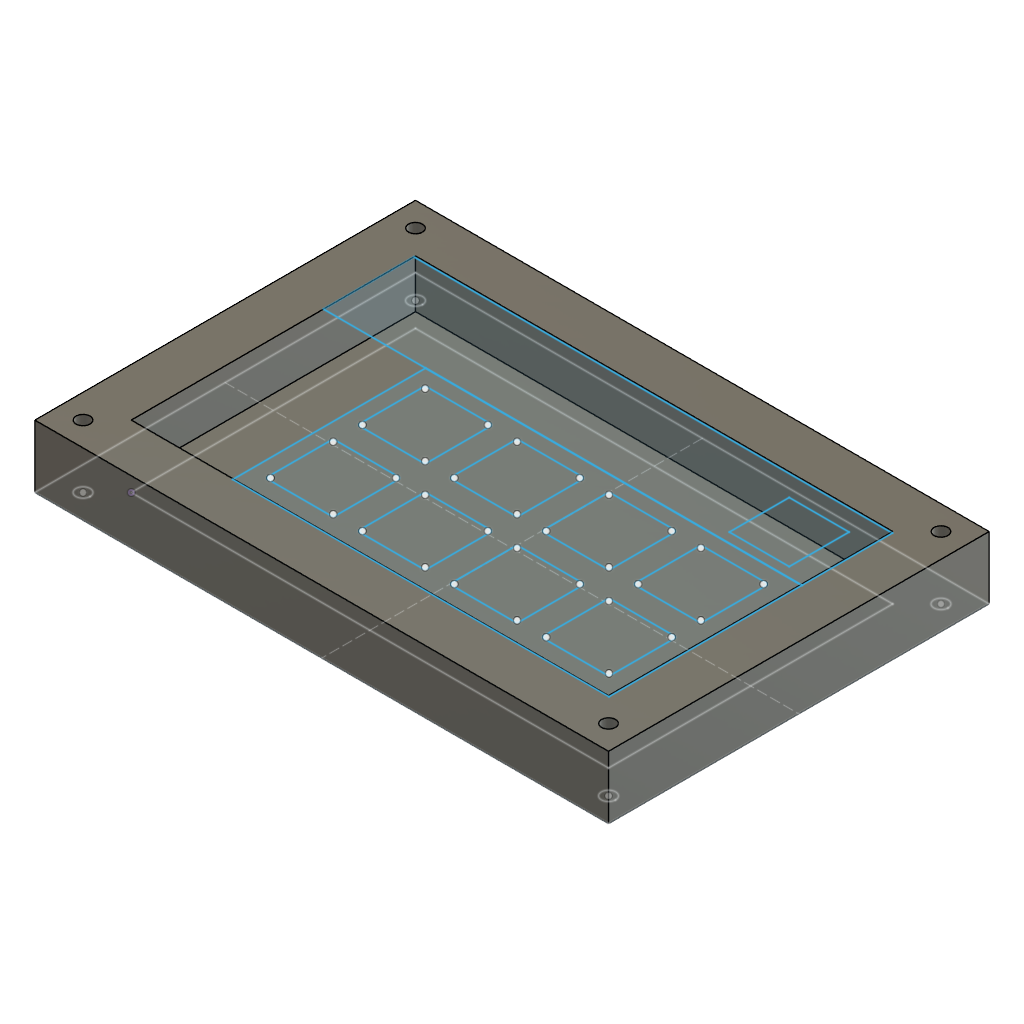
hackpad (Autodesk Fusion 360 design; units mm, degrees)
part number: 2026-11-01-11-27-36-665
Autodesk Fusion 360 part; units mm, degrees
sketch "스케치1" plane through (0, 0, 0) normal (0, 1, 0) x (1, 0, 0)
  line L0 (0, 0) -> (98.9, 0)
  line L1 (98.9, 0) -> (98.9, 58.9)
  line L2 (98.9, 58.9) -> (0, 58.9)
  line L3 (0, 58.9) -> (0, 0)
  line L4 (-10, -10) -> (108.9, -10)
  line L5 (108.9, -10) -> (108.9, 68.9)
  line L6 (108.9, 68.9) -> (-10, 68.9)
  line L7 (-10, 68.9) -> (-10, -10)
  line L8 (49.45, 68.9) -> (49.45, -10) construction
  line L9 (-10, 29.45) -> (108.9, 29.45) construction
  circle A0 centre (-5, 63.9) radius 1.45
  circle A1 centre (103.9, 63.9) radius 1.45
  circle A2 centre (-5, -5) radius 1.45
  circle A3 centre (103.9, -5) radius 1.45
  dimension "d1" = 98.9
  dimension "d2" = 58.9
  dimension "d3" = 118.9
  dimension "d4" = 78.9
  dimension "d5" = 10
  dimension "d6" = 10
  dimension "d7" = 2.9
  dimension "d8" = 5
  dimension "d9" = 5
  dimension "d10" = 2.9
  dimension "d11" = 2.9
  dimension "d12" = 2.9
  constraint horizontal L0
  constraint vertical L1
  constraint horizontal L2
  constraint vertical L3
  constraint coincident L0.start L3.end
  constraint horizontal L4
  constraint vertical L5
  constraint horizontal L6
  constraint vertical L7
  constraint midpoint L6 L8.start
  constraint midpoint L4 L8.end
  constraint midpoint L7 L9.start
  constraint midpoint L5 L9.end
  constraint symmetric L8 A0 A1
  constraint symmetric L9 A0.centre A2.centre
  constraint symmetric L9 A1.centre A3.centre
  measures "d1" distance of L0.start L0.end
  measures "d2" distance of L0.start L2.end
  measures "d3" distance of L4.start L4.end
  measures "d4" distance of L4.start L6.end
  measures "d5" distance of L2 L6
  measures "d6" distance of L3 L7
  measures "d7" diameter of A0
  measures "d8" distance of L6 A0.centre
  measures "d9" distance of L7 A0.centre
  measures "d10" diameter of A1
  measures "d11" diameter of A2
  measures "d12" diameter of A3
extrude "Extrude1" add sketch "스케치1" along normal blind 3 contours L0 L1 L2 L3 | L4 L5 L6 L7
extrude "Extrude2" add sketch "스케치1" along normal blind 10 from surface at 3
sketch "plate-2026-11-01T02_40_03.895Z" plane through (0, 13, 0) normal (0, 1, 0) x (0, 0, 1)
  line L0 (-3.525, 94.975) -> (-3.525, 81.975)
  line L1 (-17.525, 94.975) -> (-17.525, 81.975)
  line L2 (-4.025, 95.475) -> (-17.025, 95.475)
  line L3 (-4.025, 81.475) -> (-17.025, 81.475)
  arc A0 (-3.525, 94.975) -> (-4.025, 95.475) centre (-4.025, 94.975) ccw
  arc A1 (-4.025, 81.475) -> (-3.525, 81.975) centre (-4.025, 81.975) ccw
  arc A2 (-17.025, 95.475) -> (-17.525, 94.975) centre (-17.025, 94.975) ccw
  arc A3 (-17.525, 81.975) -> (-17.025, 81.475) centre (-17.025, 81.975) ccw
  line L4 (-3.525, 75.925) -> (-3.525, 62.925)
  line L5 (-17.525, 75.925) -> (-17.525, 62.925)
  line L6 (-4.025, 76.425) -> (-17.025, 76.425)
  line L7 (-4.025, 62.425) -> (-17.025, 62.425)
  arc A4 (-3.525, 75.925) -> (-4.025, 76.425) centre (-4.025, 75.925) ccw
  arc A5 (-4.025, 62.425) -> (-3.525, 62.925) centre (-4.025, 62.925) ccw
  arc A6 (-17.025, 76.425) -> (-17.525, 75.925) centre (-17.025, 75.925) ccw
  arc A7 (-17.525, 62.925) -> (-17.025, 62.425) centre (-17.025, 62.925) ccw
  line L8 (-3.525, 56.875) -> (-3.525, 43.875)
  line L9 (-17.525, 56.875) -> (-17.525, 43.875)
  line L10 (-4.025, 57.375) -> (-17.025, 57.375)
  line L11 (-4.025, 43.375) -> (-17.025, 43.375)
  arc A8 (-3.525, 56.875) -> (-4.025, 57.375) centre (-4.025, 56.875) ccw
  arc A9 (-4.025, 43.375) -> (-3.525, 43.875) centre (-4.025, 43.875) ccw
  arc A10 (-17.025, 57.375) -> (-17.525, 56.875) centre (-17.025, 56.875) ccw
  arc A11 (-17.525, 43.875) -> (-17.025, 43.375) centre (-17.025, 43.875) ccw
  line L12 (-3.525, 37.825) -> (-3.525, 24.825)
  line L13 (-17.525, 37.825) -> (-17.525, 24.825)
  line L14 (-4.025, 38.325) -> (-17.025, 38.325)
  line L15 (-4.025, 24.325) -> (-17.025, 24.325)
  arc A12 (-3.525, 37.825) -> (-4.025, 38.325) centre (-4.025, 37.825) ccw
  arc A13 (-4.025, 24.325) -> (-3.525, 24.825) centre (-4.025, 24.825) ccw
  arc A14 (-17.025, 38.325) -> (-17.525, 37.825) centre (-17.025, 37.825) ccw
  arc A15 (-17.525, 24.825) -> (-17.025, 24.325) centre (-17.025, 24.825) ccw
  line L16 (-22.575, 94.975) -> (-22.575, 81.975)
  line L17 (-36.575, 94.975) -> (-36.575, 81.975)
  line L18 (-23.075, 95.475) -> (-36.075, 95.475)
  line L19 (-23.075, 81.475) -> (-36.075, 81.475)
  arc A16 (-22.575, 94.975) -> (-23.075, 95.475) centre (-23.075, 94.975) ccw
  arc A17 (-23.075, 81.475) -> (-22.575, 81.975) centre (-23.075, 81.975) ccw
  arc A18 (-36.075, 95.475) -> (-36.575, 94.975) centre (-36.075, 94.975) ccw
  arc A19 (-36.575, 81.975) -> (-36.075, 81.475) centre (-36.075, 81.975) ccw
  line L20 (-22.575, 75.925) -> (-22.575, 62.925)
  line L21 (-36.575, 75.925) -> (-36.575, 62.925)
  line L22 (-23.075, 76.425) -> (-36.075, 76.425)
  line L23 (-23.075, 62.425) -> (-36.075, 62.425)
  arc A20 (-22.575, 75.925) -> (-23.075, 76.425) centre (-23.075, 75.925) ccw
  arc A21 (-23.075, 62.425) -> (-22.575, 62.925) centre (-23.075, 62.925) ccw
  arc A22 (-36.075, 76.425) -> (-36.575, 75.925) centre (-36.075, 75.925) ccw
  arc A23 (-36.575, 62.925) -> (-36.075, 62.425) centre (-36.075, 62.925) ccw
  line L24 (-22.575, 56.875) -> (-22.575, 43.875)
  line L25 (-36.575, 56.875) -> (-36.575, 43.875)
  line L26 (-23.075, 57.375) -> (-36.075, 57.375)
  line L27 (-23.075, 43.375) -> (-36.075, 43.375)
  arc A24 (-22.575, 56.875) -> (-23.075, 57.375) centre (-23.075, 56.875) ccw
  arc A25 (-23.075, 43.375) -> (-22.575, 43.875) centre (-23.075, 43.875) ccw
  arc A26 (-36.075, 57.375) -> (-36.575, 56.875) centre (-36.075, 56.875) ccw
  arc A27 (-36.575, 43.875) -> (-36.075, 43.375) centre (-36.075, 43.875) ccw
  line L28 (-22.575, 37.825) -> (-22.575, 24.825)
  line L29 (-36.575, 37.825) -> (-36.575, 24.825)
  line L30 (-23.075, 38.325) -> (-36.075, 38.325)
  line L31 (-23.075, 24.325) -> (-36.075, 24.325)
  arc A28 (-22.575, 37.825) -> (-23.075, 38.325) centre (-23.075, 37.825) ccw
  arc A29 (-23.075, 24.325) -> (-22.575, 24.825) centre (-23.075, 24.825) ccw
  arc A30 (-36.075, 38.325) -> (-36.575, 37.825) centre (-36.075, 37.825) ccw
  arc A31 (-36.575, 24.825) -> (-36.075, 24.325) centre (-36.075, 24.825) ccw
  line L32 (-39.825, 99.175) -> (-39.825, 21.175)
  line L33 (0.175, 99.175) -> (0.175, 21.175)
  line L34 (-39.825, 99.175) -> (0.175, 99.175)
  line L35 (-39.825, 21.175) -> (0.175, 21.175)
  line L36 (-39.825, 99.175) -> (-58.575, 99.175)
  line L37 (-58.575, 99.175) -> (-58.575, 0)
  line L38 (-58.575, 0) -> (-39.825, 0)
  line L39 (-39.825, 0) -> (-39.825, 99.175)
  line L40 (-41.875, 94.475) -> (-54.275, 94.475)
  line L41 (-54.275, 94.475) -> (-54.275, 82.075)
  line L42 (-54.275, 82.075) -> (-41.875, 82.075)
  line L43 (-41.875, 82.075) -> (-41.875, 94.475)
  dimension "d18" = 3.7
  dimension "d19" = 3.7
  dimension "d20" = 3.7
  dimension "d21" = 3.7
  dimension "d22" = 3.7
  dimension "d23" = 3.7
  dimension "d24" = 12.4
  dimension "d25" = 12.4
  dimension "d26" = 5.3
  dimension "d28" = 4.3
  dimension "d29" = 4.7
  constraint horizontal L36
  constraint vertical L37
  constraint horizontal L38
  constraint vertical L39
  constraint horizontal L40
  constraint vertical L41
  constraint horizontal L42
  constraint vertical L43
  measures "d18" distance of L0 L33
  measures "d19" distance of L4 L33
  measures "d20" distance of L8 L33
  measures "d21" distance of L12 L33
  measures "d22" distance of L18 L34
  measures "d23" distance of L2 L34
  measures "d24" distance of L40.start L40.end
  measures "d25" distance of L40.start L42.end
  measures "d26" distance of L17 L43
  measures "d28" distance of L37 L41
  measures "d29" distance of L34 L40
